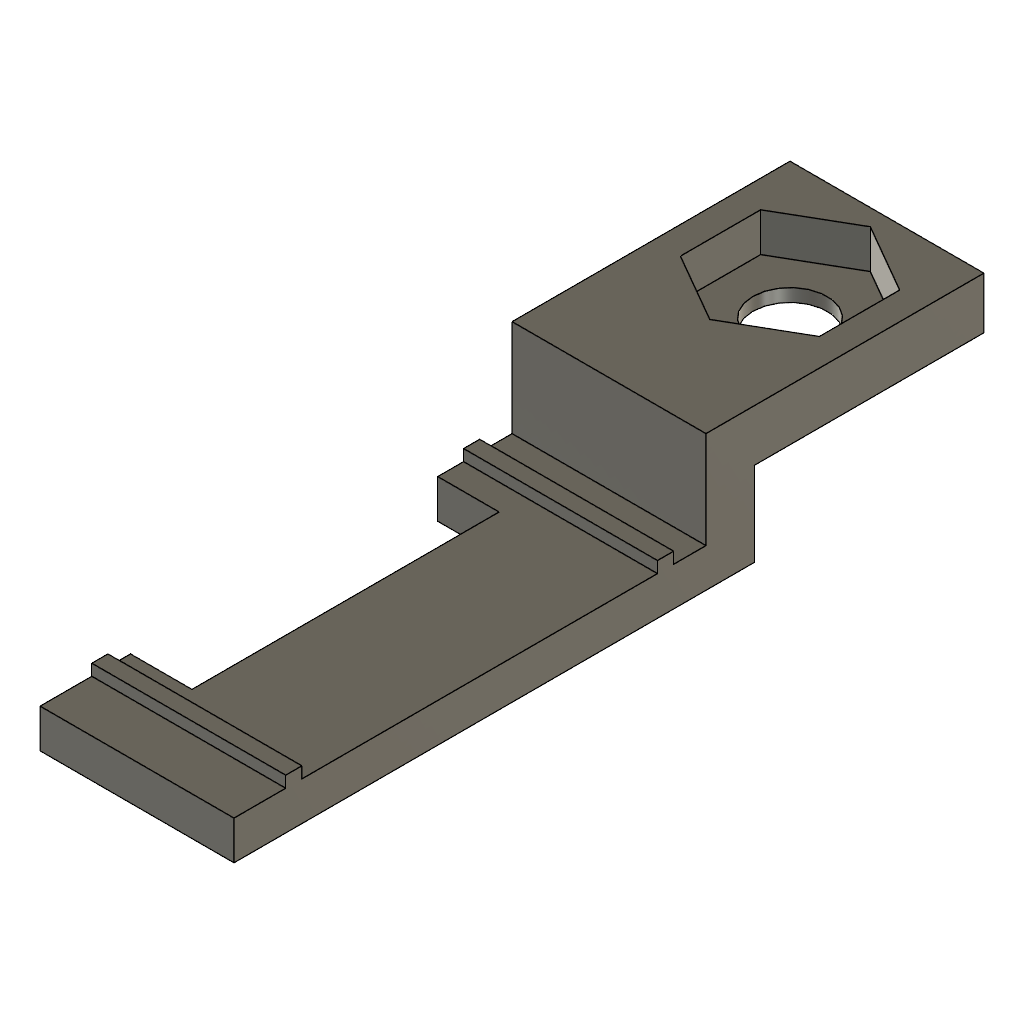
PW67_OLED_Clip_A (Autodesk Fusion 360 design; units mm, degrees)
part number: 2026-10-11-22-41-57-189
Autodesk Fusion 360 part; units mm, degrees
ref_plane "WorkPlane1" through (0, 0, 14.065) normal (0, 0, 1) x (1, 0, 0)
sketch "PCB underside clearance spine" plane through (0, 0, 14.065) normal (0, 0, 1) x (1, 0, 0)
  line L0 (66.9, -45.4) -> (72.9, -45.4)
  line L1 (72.9, -45.4) -> (72.9, -29.3)
  line L2 (72.9, -29.3) -> (66.9, -29.3)
  line L3 (66.9, -29.3) -> (66.9, -45.4)
  dimension "d140" = 6
  dimension "d141" = 16.1
  dimension "d142" = 66.9
  dimension "d143" = 45.4
  measures "d140" horizontal distance of L0.start L1.end
  measures "d141" vertical distance of L0.start L1.end
  measures "d142" horizontal distance of origin L0.start
  measures "d143" vertical distance of origin L0.start
extrude "PCB underside clearance spine (1)" add sketch "PCB underside clearance spine" along normal blind 1.2
ref_plane "WorkPlane2" through (0, 0, 15.265) normal (0, 0, 1) x (1, 0, 0)
sketch "Bare PCB retention pad" plane through (0, 0, 15.265) normal (0, 0, 1) x (1, 0, 0)
  line L0 (66.9, -43.8) -> (72.9, -43.8)
  line L1 (72.9, -43.8) -> (72.9, -43.3)
  line L2 (72.9, -43.3) -> (66.9, -43.3)
  line L3 (66.9, -43.3) -> (66.9, -43.8)
  dimension "d148" = 6
  dimension "d149" = 0.5
  dimension "d150" = 66.9
  dimension "d151" = 43.8
  measures "d148" horizontal distance of L0.start L1.end
  measures "d149" vertical distance of L0.start L1.end
  measures "d150" horizontal distance of origin L0.start
  measures "d151" vertical distance of origin L0.start
extrude "Bare PCB retention pad (1)" add sketch "Bare PCB retention pad" along normal blind 0.35
ref_plane "WorkPlane3" through (0, 0, 15.265) normal (0, 0, 1) x (1, 0, 0)
sketch "Bare PCB retention pad (1)" plane through (0, 0, 15.265) normal (0, 0, 1) x (1, 0, 0)
  line L0 (66.9, -32.3) -> (72.9, -32.3)
  line L1 (72.9, -32.3) -> (72.9, -31.8)
  line L2 (72.9, -31.8) -> (66.9, -31.8)
  line L3 (66.9, -31.8) -> (66.9, -32.3)
  dimension "d156" = 6
  dimension "d157" = 0.5
  dimension "d158" = 66.9
  dimension "d159" = 32.3
  measures "d156" horizontal distance of L0.start L1.end
  measures "d157" vertical distance of L0.start L1.end
  measures "d158" horizontal distance of origin L0.start
  measures "d159" vertical distance of origin L0.start
extrude "Bare PCB retention pad (2)" add sketch "Bare PCB retention pad (1)" along normal blind 0.35
ref_plane "WorkPlane4" through (0, 0, 15.265) normal (0, 0, 1) x (1, 0, 0)
sketch "Stepped neck above plate" plane through (0, 0, 15.265) normal (0, 0, 1) x (1, 0, 0)
  line L0 (66.9, -30.8) -> (72.9, -30.8)
  line L1 (72.9, -30.8) -> (72.9, -29.3)
  line L2 (72.9, -29.3) -> (66.9, -29.3)
  line L3 (66.9, -29.3) -> (66.9, -30.8)
  dimension "d164" = 6
  dimension "d165" = 1.5
  dimension "d166" = 66.9
  dimension "d167" = 30.8
  measures "d164" horizontal distance of L0.start L1.end
  measures "d165" vertical distance of L0.start L1.end
  measures "d166" horizontal distance of origin L0.start
  measures "d167" vertical distance of origin L0.start
extrude "Stepped neck above plate (1)" add sketch "Stepped neck above plate" along normal blind 3
ref_plane "WorkPlane5" through (0, 0, 16.665) normal (0, 0, 1) x (1, 0, 0)
sketch "M2 removable fastening tab" plane through (0, 0, 16.665) normal (0, 0, 1) x (1, 0, 0)
  line L0 (66.9, -29.4) -> (72.9, -29.4)
  line L1 (72.9, -29.4) -> (72.9, -22.2)
  line L2 (72.9, -22.2) -> (66.9, -22.2)
  line L3 (66.9, -22.2) -> (66.9, -29.4)
  dimension "d172" = 6
  dimension "d173" = 7.2
  dimension "d174" = 66.9
  dimension "d175" = 29.4
  measures "d172" horizontal distance of L0.start L1.end
  measures "d173" vertical distance of L0.start L1.end
  measures "d174" horizontal distance of origin L0.start
  measures "d175" vertical distance of origin L0.start
extrude "M2 removable fastening tab (1)" add sketch "M2 removable fastening tab" along normal blind 1.6
ref_plane "WorkPlane6" through (0, 0, 17.065) normal (0, 0, 1) x (1, 0, 0)
sketch "M2 hex nut trap - 4.3 mm AF" plane through (0, 0, 17.065) normal (0, 0, 1) x (1, 0, 0)
  line L0 (72.05, -23.9587) -> (69.9, -22.7174)
  line L1 (69.9, -22.7174) -> (67.75, -23.9587)
  line L2 (67.75, -23.9587) -> (67.75, -26.4413)
  line L3 (67.75, -26.4413) -> (69.9, -27.6826)
  line L4 (69.9, -27.6826) -> (72.05, -26.4413)
  line L5 (72.05, -26.4413) -> (72.05, -23.9587)
  circle A0 centre (69.9, -25.2) radius 2.4826 construction
  dimension "d266" = 4.9652
  dimension "d267" = 69.9
  constraint coincident L0.end L1.start
  constraint coincident L1.end L2.start
  constraint coincident L2.end L3.start
  constraint coincident L3.end L4.start
  constraint coincident L4.end L5.start
  constraint coincident L0.start L5.end
  constraint coincident L0.start A0
  constraint coincident L0.end A0
  constraint coincident L1.end A0
  constraint coincident L2.end A0
  constraint coincident L3.end A0
  constraint coincident L4.end A0
  constraint equal L0 L1
  constraint equal L0 L2
  constraint equal L0 L3
  constraint equal L0 L4
  constraint equal L0 L5
  constraint vertical L2
  measures "d266" diameter of A0
  measures "d267" horizontal distance of origin A0.centre
extrude "M2 captive nut pocket" cut sketch "M2 hex nut trap - 4.3 mm AF" along normal blind 1.3
ref_plane "WorkPlane7" through (0, 0, 16.665) normal (0, 0, 1) x (1, 0, 0)
sketch "M2 clip clearance A" plane through (0, 0, 16.665) normal (0, 0, 1) x (1, 0, 0)
  circle A0 centre (69.9, -25.2) radius 1.15
  dimension "d189" = 2.3
  dimension "d269" = 69.9
  measures "d189" diameter of A0
  measures "d269" horizontal distance of origin A0.centre
extrude "M2 clip clearance A (1)" cut sketch "M2 clip clearance A" along normal blind 1.7
ref_plane "WorkPlane8" through (0, 0, 14.065) normal (0, 0, 1) x (1, 0, 0)
sketch "OLED soldered-wire exit notch - 9.5 mm pad fanout" plane through (0, 0, 14.065) normal (0, 0, 1) x (1, 0, 0)
  line L0 (66.8, -42.6) -> (68.8, -42.6)
  line L1 (68.8, -42.6) -> (68.8, -33.1)
  line L2 (68.8, -33.1) -> (66.8, -33.1)
  line L3 (66.8, -33.1) -> (66.8, -42.6)
extrude "OLED soldered-wire exit notch" cut sketch "OLED soldered-wire exit notch - 9.5 mm pad fanout" along normal blind 1.2
equation "d138 = ( oledBracketBottomZ ) - 0 mm"
equation "d142 = oledScrewLeftX - ( 6 mm ) / 2"
equation "d143 = -( -45.4 mm )"
equation "d144 = oledBracketThickness"
equation "d146 = ( oledBracketBottomZ + oledBracketThickness ) - 0 mm"
equation "d150 = oledScrewLeftX - ( 6 mm ) / 2"
equation "d151 = -( -43.8 mm )"
equation "d152 = oledContactTopZ - oledBracketBottomZ - oledBracketThickness"
equation "d154 = ( oledBracketBottomZ + oledBracketThickness ) - 0 mm"
equation "d158 = oledScrewLeftX - ( 6 mm ) / 2"
equation "d159 = -( -32.3 mm )"
equation "d160 = oledContactTopZ - oledBracketBottomZ - oledBracketThickness"
equation "d162 = ( oledBracketBottomZ + oledBracketThickness ) - 0 mm"
equation "d166 = oledScrewLeftX - ( 6 mm ) / 2"
equation "d167 = -( -30.8 mm )"
equation "d168 = oledEarBottomZ + oledEarThickness - oledBracketBottomZ - oledBracketThickness"
equation "d170 = ( oledEarBottomZ ) - 0 mm"
equation "d174 = oledScrewLeftX - 3 mm"
equation "d175 = -( oledScrewY - 4.2 mm )"
equation "d176 = oledEarThickness"
equation "d178 = ( oledEarBottomZ + oledEarThickness - oledNutDepth ) - 0 mm"
equation "d180 = oledNutDepth + 0.1 mm"
equation "d187 = ( oledEarBottomZ ) - 0 mm"
equation "d189 = oledScrewClearance"
equation "d190 = oledEarThickness + 0.1 mm"
equation "d266 = 2 * oledNutAF / sqrt(3)"
equation "d267 = oledScrewLeftX"
equation "d268 = -oledScrewY"
equation "d269 = oledScrewLeftX"
equation "d270 = -oledScrewY"
equation "d292 = oledBracketBottomZ"
equation "d294 = oledBracketThickness"
equation "oledPCBThickness = 1.2 mm" comment "PW67 OLED; supplier tolerances and physical module must be verified"
equation "oledFrameBottomZ = 16.365 mm" comment "PW67 OLED; supplier tolerances and physical module must be verified"
equation "oledRecessDepth = 0.6 mm" comment "PW67 OLED; supplier tolerances and physical module must be verified"
equation "oledPCBTopZ = oledFrameBottomZ + oledRecessDepth" comment "PW67 OLED; supplier tolerances and physical module must be verified"
equation "oledBracketThickness = 1.2 mm" comment "PW67 OLED; supplier tolerances and physical module must be verified"
equation "oledBracketBottomZ = 14.065 mm" comment "PW67 OLED; supplier tolerances and physical module must be verified"
equation "oledRetentionGap = 0.15 mm" comment "PW67 OLED; supplier tolerances and physical module must be verified"
equation "oledContactTopZ = oledPCBTopZ - oledPCBThickness - oledRetentionGap" comment "PW67 OLED; supplier tolerances and physical module must be verified"
equation "oledScrewLeftX = 69.9 mm" comment "PW67 OLED; supplier tolerances and physical module must be verified"
equation "oledScrewY = -25.2 mm" comment "PW67 OLED; supplier tolerances and physical module must be verified"
equation "oledScrewClearance = 2.3 mm" comment "PW67 OLED; supplier tolerances and physical module must be verified"
equation "oledEarBottomZ = 16.665 mm" comment "PW67 OLED; supplier tolerances and physical module must be verified"
equation "oledEarThickness = 1.6 mm" comment "PW67 OLED; supplier tolerances and physical module must be verified"
equation "oledNutAF = 4.3 mm" comment "PW67 OLED; supplier tolerances and physical module must be verified"
equation "oledNutDepth = 1.2 mm" comment "PW67 OLED; supplier tolerances and physical module must be verified"
named bodies: "Removable OLED retainer A"
